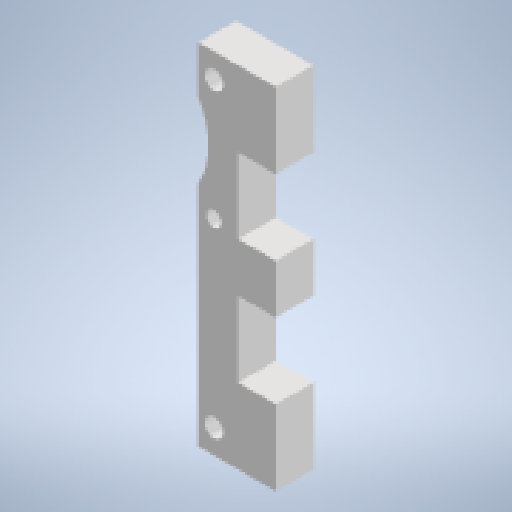
# Autodesk Inventor part: NeckSide
Saved by Autodesk Inventor 2025.2 (Build 292293000, 293)
## iProperties
Created: 2025-06-28
Part Number: NeckSide
Material: Generic
Document SubType Name: Modeling
Designer: ricoa
Density: 1 g/cm^3
Appearance: Default
Author: ricoa
Autodesk Inventor part; units mm, degrees
ref_plane "YZ Plane" through (0, 0, 0) normal (1, 0, 0) x (0, 1, 0)
ref_plane "XZ Plane" through (0, 0, 0) normal (0, 1, 0) x (-1, 0, 0)
ref_plane "XY Plane" through (0, 0, 0) normal (0, 0, 1) x (1, 0, 0)
sketch "Sketch1" plane through (0, 0, 0) normal (0, 0, 1) x (1, 0, 0)
  circle A0 centre (-14.25, 35.25) radius 1 projected
  circle A1 centre (-3.25, 27.25) radius 1 projected
  circle A2 centre (-3.25, 43.25) radius 1.25
  circle A3 centre (-3.25, 3.25) radius 1.25
  circle A4 centre (-14.25, 35.25) radius 9.75 projected
  circle A5 centre (-14.25, 35.25) radius 10.25
  line L0 (-26.5, 46.5) -> (-2, 46.5) projected
  line L1 (-2, 0) -> (-26.5, 0) projected
  line L2 (-3.25, 43.25) -> (-5.25, 43.25) construction
  line L3 (-5.25, 43.25) -> (-5.25, 40.1554)
  line L4 (-5.25, 43.25) -> (-5.25, 46.5)
  line L5 (-5.25, 30.3446) -> (-5.25, 0)
  line L6 (0, 44.5) -> (0, 2) projected
  line L7 (-5.25, 46.5) -> (0, 46.5)
  line L8 (0, 46.5) -> (5, 46.5)
  line L9 (5, 46.5) -> (5, 36.5)
  line L10 (5, 36.5) -> (0, 36.5)
  line L11 (-2, 0) -> (5, 0)
  line L12 (5, 0) -> (5, 10)
  line L13 (5, 10) -> (0, 10)
  line L14 (0, 23.25) -> (8.8681, 23.25) construction
  line L15 (0, 36.5) -> (0, 26.5)
  line L16 (0, 26.5) -> (5, 26.5)
  line L17 (5, 26.5) -> (5, 23.25)
  line L18 (0, 10) -> (0, 20)
  line L19 (0, 20) -> (5, 20)
  line L20 (5, 20) -> (5, 23.25)
  point P0 (0, 0)
  point P1 (-28.25, 44.3964)
  point P2 (-9, 2)
  dimension "d0" = 2.5
  dimension "d1" = 2.5
  dimension "d3" = 2
  dimension "d4" = 5
  dimension "d5" = 10
  dimension "d6" = 10
  dimension "d7" = 10
  dimension "d8" = 10
  constraints: 36 end point, 13 point on line, 8 perpendicular, 3 centre point, 2 horizontal, 2 point on circle, 1 collinear, 1 midpoint
  measures "d0" diameter of A2
  measures "d1" diameter of A3
  measures "d3" distance of L2.start L2.end
  measures "d4" distance of L7.end L8.end
  measures "d5" distance of L8.end L9.end
  measures "d6" distance of L11.end L12.end
  measures "d7" distance of L10.end L15.end
  measures "d8" distance of L13.end L18.end
extrude "Extrusion1" add sketch "Sketch1" along normal blind 5 contours A5 L3 L4 L0 L7 L8 L9 L10 L6 L13 L12 L11 L1 L5 | L6 L16 L17 L20 L19
body "Solid1"
